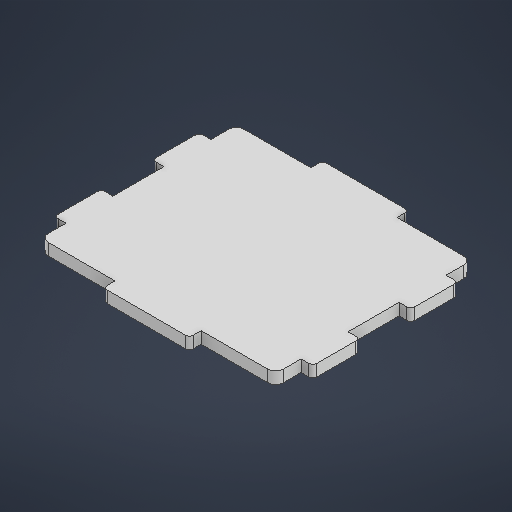
# Autodesk Inventor part: SecondRxBase
Saved by Autodesk Inventor 2027.1 (Build 311270010, 270A)
## iProperties
Created: 2026-10-18
Part Number: SecondRxBase
Material: Generic
Document SubType Name: Modeling
Designer: SDS Scholar
Density: 1 g/cm^3
Appearance: Default
Author: SDS Scholar
Autodesk Inventor part; units mm, degrees
ref_plane "YZ Plane" through (0, 0, 0) normal (1, 0, 0) x (0, 1, 0)
ref_plane "XZ Plane" through (0, 0, 0) normal (0, 1, 0) x (-1, 0, 0)
ref_plane "XY Plane" through (0, 0, 0) normal (0, 0, 1) x (1, 0, 0)
sketch "Sketch1" plane through (0, 0, 0) normal (0, 1, 0) x (-1, 0, 0)
  line L0 (30, 25) -> (-30, 25)
  line L1 (-30, 25) -> (-30, -25)
  line L2 (-30, -25) -> (30, -25)
  line L3 (30, -25) -> (30, 25)
  line L4 (11, -25) -> (-11, -25)
  line L5 (-11, -25) -> (-11, -28)
  line L6 (-11, -28) -> (11, -28)
  line L7 (11, -28) -> (11, -25)
  line L8 (30, 0) -> (-30, 0) construction
  line L9 (30, -6.5) -> (33, -6.5)
  line L10 (33, -6.5) -> (33, -18.5)
  line L11 (33, -18.5) -> (30, -18.5)
  line L12 (30, -18.5) -> (30, -6.5)
  line L13 (0, 25) -> (0, -25) construction
  line L14 (-30, -6.5) -> (-33, -6.5)
  line L15 (-33, -6.5) -> (-33, -18.5)
  line L16 (-33, -18.5) -> (-30, -18.5)
  line L17 (-11, 25) -> (-11, 28)
  line L18 (-11, 28) -> (11, 28)
  line L19 (11, 28) -> (11, 25)
  line L20 (30, 6.5) -> (33, 6.5)
  line L21 (33, 6.5) -> (33, 18.5)
  line L22 (33, 18.5) -> (30, 18.5)
  line L23 (-33, 6.5) -> (-33, 18.5)
  line L24 (-30, 6.5) -> (-33, 6.5)
  line L25 (-33, 18.5) -> (-30, 18.5)
  point P0 (0, 0)
  point P1 (0, -28)
  point P2 (33, -12.5)
  dimension "d0" = 50
  dimension "d1" = 60
  dimension "d2" = 22
  dimension "d3" = 3
  dimension "d4" = 12
  dimension "d5" = 3
  dimension "d6" = 12.5
  constraints: 52 end point, 16 symmetric about line, 6 midpoint, 6 parallel, 3 horizontal, 3 perpendicular, 2 point on line, 2 vertical alignment, 1 horizontal alignment, 1 vertical
  measures "d0" distance of L0.end L1.end
  measures "d1" distance of L0.start L0.end
  measures "d2" distance of L5.end L6.end
  measures "d3" distance of L6.end L4.start
  measures "d4" distance of L9.end L10.end
  measures "d5" distance of L10.end L11.end
  measures "d6" distance from line of L2 point (33, -12.5)
extrude "Extrusion1" add sketch "Sketch1" along normal blind 3
fillet "Fillet1" radius 2 4 edges at (30, 1.5, 25) (30, 1.5, -25) (-30, 1.5, 25) (-30, 1.5, -25)
fillet "Fillet2" radius 1 12 edges at (-33, 1.5, -18.5) (-33, 1.5, -6.5) (-33, 1.5, 6.5) (-33, 1.5, 18.5) (-11, 1.5, -28) (11, 1.5, -28) (-11, 1.5, 28) (11, 1.5, 28) (33, 1.5, 18.5) (33, 1.5, 6.5) (33, 1.5, -6.5) (33, 1.5, -18.5)
equation "\"d6\" = 0.25 * d0"
body "Solid1"
